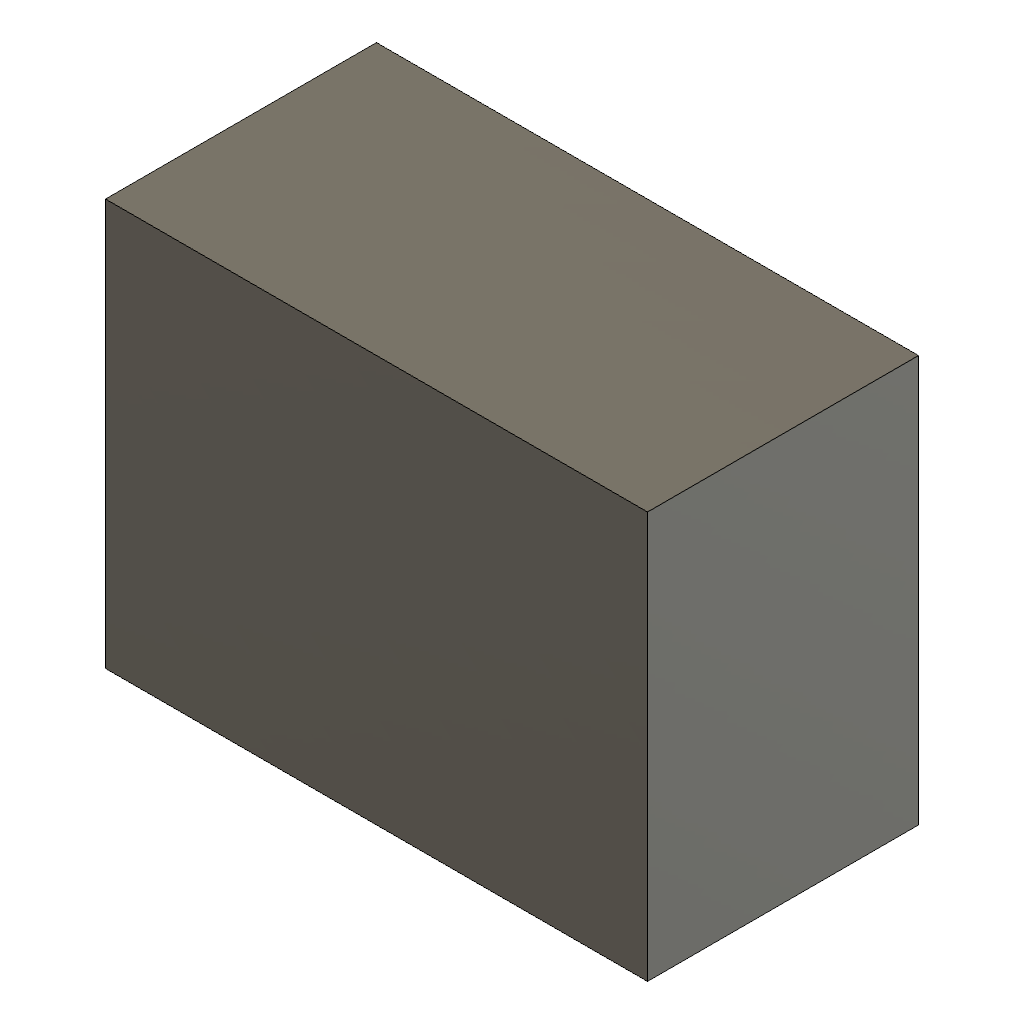
delete_hole_face (Autodesk Fusion 360 design; units mm, degrees)
part number: 2026-10-20-20-19-13-316
Autodesk Fusion 360 part; units mm, degrees
sketch "Sketch1" plane through (0, 0, 0) normal (0, 0, 1) x (1, 0, 0)
  line L0 (0, 0) -> (40, 0)
  line L1 (40, 0) -> (40, 30)
  line L2 (40, 30) -> (0, 30)
  line L3 (0, 30) -> (0, 0)
extrude "FaceEditSeed" add sketch "Sketch1" along normal blind 20
sketch "Sketch2" plane through (0, 0, 0) normal (0, 0, 1) x (1, 0, 0)
  circle A0 centre (20, 15) radius 5
extrude "Extrude2" cut sketch "Sketch2" along normal blind 20
delete_face "ProbeFaceEdit" 1 faces at (24.9938, 14.7508, 13.3333)
